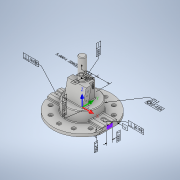
# Autodesk Inventor part: INV_nist_ctc_05_asme1_2021
Saved by Autodesk Inventor 2021 (Build 250183000, 183)
## iProperties
Created: 2016-11-28
Part Number: INV_nist_ctc_05_asme1_2021
Material: Generic
Document SubType Name: Modeling
Designer: t_liuje
Density: 1 g/cm^3
Appearance: Default
Author: t_liuje
Autodesk Inventor part; units mm, degrees
ref_plane "YZ Plane" through (0, 0, 0) normal (1, 0, 0) x (0, 1, 0)
ref_plane "XZ Plane" through (0, 0, 0) normal (0, 1, 0) x (-1, 0, 0)
sketch "Block1" plane through (0, 0, 0) normal (0, 0, 1) x (1, 0, 0)
  arc A0 (-118.2557, 65.6436) -> (-111.9926, 67.8413) centre (-115.5097, 67.8413) ccw
  line L0 (-127.7228, 75.9332) -> (-118.2557, 65.6436)
  arc A1 (-127.7228, 75.9332) -> (-128.66, 75.5676) centre (-128.1201, 75.5676) ccw
  line L1 (-128.66, 64.3242) -> (-128.66, 75.5676)
  line L2 (-131.7625, 64.3242) -> (-128.66, 64.3242)
  line L3 (-131.7625, 76.4863) -> (-131.7625, 64.3242)
  arc A2 (-126.1073, 78.7002) -> (-131.7625, 76.4863) centre (-128.5015, 76.4863) ccw
  line L4 (-115.8425, 67.5998) -> (-126.1073, 78.7002)
  arc A3 (-115.8425, 67.5998) -> (-115.1248, 67.916) centre (-115.538, 67.8813) ccw
  line L5 (-115.1248, 79.3242) -> (-115.1248, 67.916)
  line L6 (-111.9926, 79.3242) -> (-115.1248, 79.3242)
  line L7 (-111.9926, 67.8413) -> (-111.9926, 79.3242)
  arc A4 (-109.9814, 68.5199) -> (-105.7857, 64.3242) centre (-105.7857, 68.5199) ccw
  line L8 (-109.9814, 79.3242) -> (-109.9814, 68.5199)
  line L9 (-106.8491, 79.3242) -> (-109.9814, 79.3242)
  line L10 (-106.8491, 68.5199) -> (-106.8491, 79.3242)
  arc A5 (-106.8491, 68.5199) -> (-105.7566, 67.4273) centre (-105.7566, 68.5199) ccw
  line L11 (-91.0451, 67.4273) -> (-105.7566, 67.4273)
  arc A6 (-91.0451, 67.4273) -> (-91.1026, 70.2437) centre (-91.2253, 68.8325) ccw
  line L12 (-100.1544, 70.2437) -> (-91.1026, 70.2437)
  arc A7 (-100.4984, 79.3242) -> (-100.1544, 70.2437) centre (-100.4984, 74.7774) ccw
  line L13 (-74.8951, 79.3242) -> (-100.4984, 79.3242)
  line L14 (-74.8951, 76.1632) -> (-74.8951, 79.3242)
  line L15 (-81.3044, 76.1632) -> (-74.8951, 76.1632)
  line L16 (-81.3044, 64.3242) -> (-81.3044, 76.1632)
  line L17 (-84.4069, 64.3242) -> (-81.3044, 64.3242)
  line L18 (-84.4069, 76.1632) -> (-84.4069, 64.3242)
  line L19 (-100.097, 76.1632) -> (-84.4069, 76.1632)
  arc A8 (-100.097, 76.1632) -> (-100.2119, 73.3471) centre (-100.2119, 74.7575) ccw
  line L20 (-90.5852, 73.3471) -> (-100.2119, 73.3471)
  arc A9 (-90.5852, 64.3242) -> (-90.5852, 73.3471) centre (-91.3036, 68.8356) ccw
  line L21 (-105.7857, 64.3242) -> (-90.5852, 64.3242)
sketch "Block2" plane through (0, 0, 0) normal (0, 0, 1) x (1, 0, 0)
  arc A0 (33.0727, -26.2068) -> (35.2704, -32.4699) centre (35.2704, -28.9528) ccw
  line L0 (43.3622, -16.7397) -> (33.0727, -26.2068)
  arc A1 (43.3622, -16.7397) -> (42.9967, -15.8025) centre (42.9967, -16.3424) ccw
  line L1 (31.7532, -15.8025) -> (42.9967, -15.8025)
  line L2 (31.7532, -12.7) -> (31.7532, -15.8025)
  line L3 (43.9153, -12.7) -> (31.7532, -12.7)
  arc A2 (46.1293, -18.3552) -> (43.9153, -12.7) centre (43.9153, -15.961) ccw
  line L4 (35.0289, -28.62) -> (46.1293, -18.3552)
  arc A3 (35.0289, -28.62) -> (35.3451, -29.3377) centre (35.3104, -28.9245) ccw
  line L5 (46.7532, -29.3377) -> (35.3451, -29.3377)
  line L6 (46.7532, -32.4699) -> (46.7532, -29.3377)
  line L7 (35.2704, -32.4699) -> (46.7532, -32.4699)
  arc A4 (35.949, -34.4811) -> (31.7532, -38.6768) centre (35.949, -38.6768) ccw
  line L8 (46.7532, -34.4811) -> (35.949, -34.4811)
  line L9 (46.7532, -37.6134) -> (46.7532, -34.4811)
  line L10 (35.949, -37.6134) -> (46.7532, -37.6134)
  arc A5 (35.949, -37.6134) -> (34.8564, -38.7059) centre (35.949, -38.7059) ccw
  line L11 (34.8564, -53.4174) -> (34.8564, -38.7059)
  arc A6 (34.8564, -53.4174) -> (37.6728, -53.3599) centre (36.2615, -53.2372) ccw
  line L12 (37.6728, -44.3081) -> (37.6728, -53.3599)
  arc A7 (46.7532, -43.9641) -> (37.6728, -44.3081) centre (42.2065, -43.9641) ccw
  line L13 (46.7532, -69.5674) -> (46.7532, -43.9641)
  line L14 (43.5922, -69.5674) -> (46.7532, -69.5674)
  line L15 (43.5922, -63.1581) -> (43.5922, -69.5674)
  line L16 (31.7532, -63.1581) -> (43.5922, -63.1581)
  line L17 (31.7532, -60.0556) -> (31.7532, -63.1581)
  line L18 (43.5922, -60.0556) -> (31.7532, -60.0556)
  line L19 (43.5922, -44.3655) -> (43.5922, -60.0556)
  arc A8 (43.5922, -44.3655) -> (40.7762, -44.2506) centre (42.1865, -44.2506) ccw
  line L20 (40.7762, -53.8773) -> (40.7762, -44.2506)
  arc A9 (31.7532, -53.8773) -> (40.7762, -53.8773) centre (36.2647, -53.1589) ccw
  line L21 (31.7532, -38.6768) -> (31.7532, -53.8773)
  point P0 (39.2776, -39.3345)
sketch "Sketch1" plane through (0, 0, 0) normal (0, 1, 0) x (-1, 0, 0)
  line L0 (263.525, -92.8382) -> (263.525, 92.8382)
  line L1 (-263.525, -92.8382) -> (-263.525, 92.8382)
  arc A0 (-263.525, -92.8382) -> (263.525, -92.8382) centre (0, 0) ccw
  arc A1 (263.525, 92.8382) -> (-263.525, 92.8382) centre (0, 0) ccw
  dimension "d1" = 527.05
  dimension "d2" = 279.4
  dimension "d3" = 279.4
  constraints: 4 end point, 4 point on circle, 2 centre point, 2 vertical, 1 coincident, 1 parallel
  measures "d1" distance between parallel lines of L1 L0
  measures "d2" radius of A0
  measures "d3" radius of A1
extrude "Extrusion1" add sketch "Sketch1" along normal blind 25.4
sketch "Sketch2" plane through (-263.525, 0, -92.8382) normal (-1, 0, 0) x (0, 0, 1)
  line L0 (22.9882, 25.4) -> (22.9882, 44.7672)
  line L1 (162.6882, 25.4) -> (162.6882, 44.7672)
  line L2 (22.9882, 25.4) -> (162.6882, 25.4)
  line L3 (0, 25.4) -> (185.6764, 25.4) projected
  line L4 (48.8708, 52.3363) -> (136.8056, 52.3363)
  line L5 (92.8382, 0) -> (92.8382, 107.4223) construction
  arc A0 (162.6882, 44.7672) -> (136.8056, 52.3363) centre (92.8382, -146.05) ccw
  arc A1 (48.8708, 52.3363) -> (22.9882, 44.7672) centre (92.8382, -146.05) ccw
  dimension "d6" = 139.7
  dimension "d8" = 171.45
  dimension "d9" = 87.9348
  dimension "d10" = 203.2
  dimension "d11" = 203.2
  constraints: 10 end point, 4 point on circle, 3 vertical, 2 centre point, 1 collinear, 1 horizontal, 1 parallel, 1 other
  measures "d6" distance of L0.start L1.start
  measures "d8" distance from line of L2 A0.centre
  measures "d9" distance of L4.start L4.end
  measures "d10" radius of A1
  measures "d11" radius of A0
extrude "Extrusion2" add sketch "Sketch2" against normal up to surface (527.05 mm away)
sketch "Sketch3" plane through (0, 25.4, 0) normal (0, 1, 0) x (1, 0, 0)
  circle A0 centre (0, 0) radius 152.4
  dimension "d14" = 304.8
  constraints: 1 centre point, 1 coincident
  measures "d14" diameter of A0
extrude "Extrusion3" add sketch "Sketch3" along normal blind 101.6
sketch "Sketch4" plane through (0, 0, 0) normal (1, 0, 0) x (0, 1, 0)
  line L0 (0, 0) -> (321.0968, 0) construction
  line L1 (279.4, 50.8) -> (279.4, 0)
  line L2 (279.4, 50.8) -> (127, 84.5863)
  line L3 (127, -152.4) -> (127, 152.4) projected
  line L4 (279.4, 0) -> (127, 33.7863)
  line L5 (127, 33.7863) -> (127, 84.5863)
  dimension "d17" = 50.8
  dimension "d18" = 77.5
  dimension "d19" = 152.4
  constraints: 10 end point, 2 point on line, 2 vertical, 1 horizontal, 1 parallel
  measures "d17" distance of L1.start L1.end
  measures "d18" angle of L3 L2
  measures "d19" distance between parallel lines of L3 L1
extrude "Extrusion4" add sketch "Sketch4" along normal mid plane 177.8
sketch "Sketch5" plane through (0, 127, 0) normal (0, 1, 0) x (1, 0, 0)
  line L0 (-88.9, -50.8) -> (88.9, -50.8) projected
  line L1 (0, -128.9844) -> (0, 120.0547) construction
  line L2 (-63.5, -50.8) -> (-63.5, 59.1852)
  line L3 (63.5, -50.8) -> (63.5, 59.1852)
  arc A0 (63.5, 59.1852) -> (-63.5, 59.1852) centre (0, -50.8) ccw
  line L4 (63.5, -50.8) -> (-63.5, -50.8)
  point P0 (0, 0)
  dimension "d23" = 127
  dimension "d24" = 127
  constraints: 8 end point, 3 vertical, 2 point on circle, 2 point on line, 1 centre point, 1 collinear, 1 midpoint, 1 other
  measures "d23" distance between parallel lines of L3 L2
  measures "d24" radius of A0
extrude "Extrusion5" add sketch "Sketch5" along normal up to surface (152.4 mm away)
sketch "Sketch6" plane through (-88.9, 279.4, 50.8) normal (0, 1, 0) x (1, 0, 0)
  circle A0 centre (88.9, 50.8) radius 31.75
  dimension "d27" = 63.5
  constraints: 1 centre point, 1 coincident
  measures "d27" diameter of A0
extrude "Extrusion6" add sketch "Sketch6" along normal blind 203.2
sketch "Sketch7" plane through (-263.525, 52.3363, 43.9674) normal (0, 1, 0) x (1, 0, 0)
  line L0 (0, 63.0174) -> (60.325, 63.0174)
  line L1 (60.325, 24.9174) -> (0, 24.9174)
  line L2 (0, 24.9174) -> (0, 63.0174)
  line L3 (263.525, 43.9674) -> (-126.7596, 43.9674) construction
  arc A0 (60.325, 24.9174) -> (60.325, 63.0174) centre (60.325, 43.9674) ccw
  line L4 (0, 87.9348) -> (0, 0) projected
  dimension "d31" = 38.1
  dimension "d32" = 60.325
  constraints: 8 end point, 2 horizontal, 2 point on circle, 2 tangent, 1 centre point, 1 collinear, 1 parallel, 1 other
  measures "d31" distance of L0.end L1.start
  measures "d32" distance from line of L2 A0.centre
extrude "Extrusion7" cut sketch "Sketch7" against normal blind 8.89
hole "Hole1" at (-234.95, 43.4463, 0) direction (0, -1, 0) diameter 7.9502 depth 30.48 tip angle 118
hole "Hole2" at (-203.2, 43.4463, 0) direction (0, -1, 0) diameter 7.9502 depth 30.48 tip angle 118
mirror "Mirror1" about plane through (0, 0, 0) normal (1, 0, 0) of "Hole1", "Hole2", "Extrusion7"
sketch "Sketch9" plane through (263.525, 0, 92.8382) normal (1, 0, 0) x (0, 0, -1)
  line L0 (118.2382, 43.4463) -> (67.4382, 43.4463)
  line L1 (67.4382, 43.4463) -> (67.4382, 11.6963)
  line L2 (67.4382, 11.6963) -> (118.2382, 11.6963)
  line L3 (118.2382, 11.6963) -> (118.2382, 43.4463)
  line L4 (111.8882, 43.4463) -> (73.7882, 43.4463) projected
  line L5 (118.2382, 43.4463) -> (86.4882, 11.6963)
  line L6 (111.054, 43.4463) -> (79.304, 11.6963)
  line L7 (118.2382, 36.2621) -> (93.6724, 11.6963)
  line L8 (118.2382, 29.0778) -> (100.8566, 11.6963)
  line L9 (118.2382, 21.8936) -> (108.0408, 11.6963)
  line L10 (118.2382, 14.7094) -> (115.225, 11.6963)
  line L11 (103.8698, 43.4463) -> (72.1198, 11.6963)
  line L12 (96.6856, 43.4463) -> (67.4382, 14.1989)
  line L13 (89.5014, 43.4463) -> (67.4382, 21.3831)
  line L14 (82.3172, 43.4463) -> (67.4382, 28.5673)
  line L15 (75.133, 43.4463) -> (67.4382, 35.7515)
  line L16 (67.9488, 43.4463) -> (67.4382, 42.9357)
  constraints: 30 end point, 16 point on line, 2 horizontal, 1 collinear, 1 parallel, 1 perpendicular, 10 other
fillet "Fillet1" radius 6.35 26 edges at (199.4876, 25.4, 69.85) (-199.4876, 25.4, 69.85) (0, 25.4, 152.4) (-199.4876, 25.4, -69.85) (0, 25.4, -152.4) (199.4876, 25.4, -69.85) (-135.4501, 35.0836, 69.85) (135.4501, 35.0836, 69.85) (-135.4501, 35.0836, -69.85) (135.4501, 35.0836, -69.85) (-141.1518, 48.8559, 57.4624) (-152.4, 52.3363, 0) (-141.1518, 48.8559, -57.4624) (150.7713, 52.3363, -22.2212) (150.7713, 52.3363, 22.2212) (141.1518, 48.8559, -57.4624) (141.1518, 48.8559, 57.4624) (0, 127, 84.5863) (88.9, 127, 59.1863) (63.5, 127, -12.6995) (76.2, 127, 33.7863) (0, 127, -76.2) (-63.5, 127, -12.6995) (-76.2, 127, 33.7863) (-88.9, 127, 59.1863) (-31.75, 279.4, 0)
chamfer "Chamfer1" distance 6.35 angle 45 2 edges at (-152.4, 127, 0) (-31.75, 482.6, 0)
hole "Hole3" at (-88.9, 241.3, 33.2299) direction (1, 0, 0) diameter 10.7188 depth 30.48 tip angle 118
pattern_linear "Rectangular Pattern1" count 3 spacing 35.7632 along (0, -0.976296, 0.2164396) of "Hole3"
mirror "Mirror2" about plane through (0, 0, 0) normal (1, 0, 0) of "Hole3", "Rectangular Pattern1"
sketch "Sketch8" plane through (0, 25.4, 0) normal (0, 1, 0) x (1, 0, 0)
  circle A0 centre (0, 0) radius 222.25 construction
  point P0 (0, 222.25)
  dimension "d69" = 444.5
  constraints: 1 coincident, 1 vertical alignment, 2 other
hole "Hole4" at (0, 25.4, -222.25) direction (0, -1, 0) diameter 19.05 end up to surface counterbore diameter 38.1 counterbore depth 12.7
pattern_circular "Circular Pattern1" count 3 over 60 about axis through (0, -10, 0) along (0, 1, 0) of "Hole4"
pattern_circular "Circular Pattern2" count 3 over 60 about axis through (0, -10, 0) along (0, -1, 0) of "Hole4"
mirror "Mirror3" about plane through (0, 0, 0) normal (0, 0, 1) of "Hole4", "Circular Pattern1", "Circular Pattern2"
hole "Hole5" at (0, 0, 0) direction (0, 1, 0) diameter 254 depth 101.6
fillet "Fillet2" radius 6.35 1 edges at (0, 0, 127)
sketch "Sketch10" plane through (-263.525, 0, -92.8382) normal (-1, 0, 0) x (0, 0, 1)
  line L0 (73.7882, 43.4463) -> (111.8882, 43.4463) projected
  line L1 (67.4382, 43.4463) -> (118.2382, 43.4463)
  line L2 (118.2382, 43.4463) -> (118.2382, 11.6963)
  line L3 (118.2382, 11.6963) -> (67.4382, 11.6963)
  line L4 (67.4382, 11.6963) -> (67.4382, 43.4463)
  line L5 (111.8882, 43.4463) -> (73.7882, 43.4463) projected
  line L6 (67.4382, 11.6963) -> (112.3395, 11.6963) construction
  line L7 (67.4382, 18.8805) -> (92.004, 43.4463)
  line L8 (67.4382, 26.0647) -> (84.8198, 43.4463)
  line L9 (67.4382, 33.2489) -> (77.6356, 43.4463)
  line L10 (67.4382, 40.4331) -> (70.4514, 43.4463)
  line L11 (74.6224, 11.6963) -> (106.3724, 43.4463)
  line L12 (81.8066, 11.6963) -> (113.5566, 43.4463)
  line L13 (88.9908, 11.6963) -> (118.2382, 40.9436)
  line L14 (96.175, 11.6963) -> (118.2382, 33.7594)
  line L15 (103.3592, 11.6963) -> (118.2382, 26.5752)
  line L16 (110.5434, 11.6963) -> (118.2382, 19.391)
  line L17 (117.7277, 11.6963) -> (118.2382, 12.2068)
  line L18 (67.4382, 11.6963) -> (99.1882, 43.4463)
  constraints: 32 end point, 16 point on line, 3 horizontal, 1 parallel, 1 vertical, 10 other
sketch "Sketch11" plane through (63.5, 279.4, 0) normal (1, 0, 0) x (0, 0, -1)
  line L0 (59.1852, -146.05) -> (59.1852, 0) projected
  line L1 (59.1852, 0) -> (0, 0) projected
  arc A0 (33.0727, -26.2068) -> (35.2704, -32.4699) centre (35.2704, -28.9528) ccw
  line L2 (43.3622, -16.7397) -> (33.0727, -26.2068)
  arc A1 (43.3622, -16.7397) -> (42.9967, -15.8025) centre (42.9967, -16.3424) ccw
  line L3 (31.7532, -15.8025) -> (42.9967, -15.8025)
  line L4 (31.7532, -12.7) -> (31.7532, -15.8025)
  line L5 (43.9153, -12.7) -> (31.7532, -12.7)
  arc A2 (46.1293, -18.3552) -> (43.9153, -12.7) centre (43.9153, -15.961) ccw
  line L6 (35.0289, -28.62) -> (46.1293, -18.3552)
  arc A3 (35.0289, -28.62) -> (35.3451, -29.3377) centre (35.3104, -28.9245) ccw
  line L7 (46.7532, -29.3377) -> (35.3451, -29.3377)
  line L8 (46.7532, -32.4699) -> (46.7532, -29.3377)
  line L9 (35.2704, -32.4699) -> (46.7532, -32.4699)
  arc A4 (35.949, -34.4811) -> (31.7532, -38.6768) centre (35.949, -38.6768) ccw
  line L10 (46.7532, -34.4811) -> (35.949, -34.4811)
  line L11 (46.7532, -37.6134) -> (46.7532, -34.4811)
  line L12 (35.949, -37.6134) -> (46.7532, -37.6134)
  arc A5 (35.949, -37.6134) -> (34.8564, -38.7059) centre (35.949, -38.7059) ccw
  line L13 (34.8564, -53.4174) -> (34.8564, -38.7059)
  arc A6 (34.8564, -53.4174) -> (37.6728, -53.3599) centre (36.2615, -53.2372) ccw
  line L14 (37.6728, -44.3081) -> (37.6728, -53.3599)
  arc A7 (46.7532, -43.9641) -> (37.6728, -44.3081) centre (42.2065, -43.9641) ccw
  line L15 (46.7532, -69.5674) -> (46.7532, -43.9641)
  line L16 (43.5922, -69.5674) -> (46.7532, -69.5674)
  line L17 (43.5922, -63.1581) -> (43.5922, -69.5674)
  line L18 (31.7532, -63.1581) -> (43.5922, -63.1581)
  line L19 (31.7532, -60.0556) -> (31.7532, -63.1581)
  line L20 (43.5922, -60.0556) -> (31.7532, -60.0556)
  line L21 (43.5922, -44.3655) -> (43.5922, -60.0556)
  arc A8 (43.5922, -44.3655) -> (40.7762, -44.2506) centre (42.1865, -44.2506) ccw
  line L22 (40.7762, -53.8773) -> (40.7762, -44.2506)
  arc A9 (31.7532, -53.8773) -> (40.7762, -53.8773) centre (36.2647, -53.1589) ccw
  line L23 (31.7532, -38.6768) -> (31.7532, -53.8773)
  point P0 (0, -279.4)
  dimension "d158" = 27.432
  dimension "d159" = 12.7
extrude "Extrusion9" cut sketch "Sketch11" against normal blind 2.54
ref_plane "Work Plane1" through (0, 127, -76.2) normal (0, 0, 1) x (1, 0, 0)
sketch "Sketch12" plane through (0, 127, -76.2) normal (0, 0, 1) x (1, 0, 0)
  line L0 (0, 138.5278) -> (0, 100.4278)
  dimension "d207" = 38.1
  constraints: 2 end point, 1 vertical
  measures "d207" distance of L0.start L0.end
split_face "Split1"
split_face "Split2"
body "Solid1"
